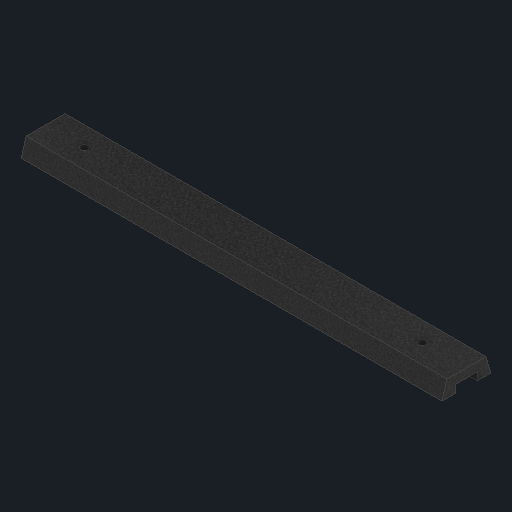
# Autodesk Inventor part: c8n_vixen_bar
Saved by Autodesk Inventor 2027.1 (Build 311270010, 270A)
## iProperties
Created: 2026-11-04
Part Number: c8n_vixen_bar
Material: Generic
Description: Vixen dovetail bar, 380 mm
Document SubType Name: Modeling
Designer: Claude (from photos)
Density: 1 g/cm^3
Appearance: Black Cast
Author: alexg
Autodesk Inventor part; units mm, degrees
ref_plane "Work Plane1" through (180, 0, 0) normal (1, 0, 0) x (0, 1, 0)
sketch "Vixen dovetail 44 wide sketch" plane through (180, 0, 0) normal (1, 0, 0) x (0, 1, 0)
  line L0 (-146, -22) -> (-146, 22)
  line L1 (-146, 22) -> (-131, 17.6005)
  line L2 (-131, 17.6005) -> (-131, -17.6005)
  line L3 (-131, -17.6005) -> (-146, -22)
  constraints: 8 end point
extrude "Vixen dovetail 44 wide" add sketch "Vixen dovetail 44 wide sketch" along normal blind 380
ref_plane "Work Plane2" through (180, 0, 0) normal (1, 0, 0) x (0, 1, 0)
sketch "Bottom channel sketch" plane through (180, 0, 0) normal (1, 0, 0) x (0, 1, 0)
  line L0 (-146, -10) -> (-139, -10)
  line L1 (-139, -10) -> (-139, 10)
  line L2 (-139, 10) -> (-146, 10)
  line L3 (-146, 10) -> (-146, -10)
  constraints: 8 end point, 2 parallel, 1 horizontal, 1 perpendicular
extrude "Bottom channel" cut sketch "Bottom channel sketch" along normal blind 380
ref_plane "Work Plane3" through (0, -146, 0) normal (0, 1, 0) x (-1, 0, 0)
sketch "Ring bolt holes sketch" plane through (0, -146, 0) normal (0, 1, 0) x (-1, 0, 0)
  circle A0 centre (-215, 0) radius 3.3
  circle A1 centre (-520, 0) radius 3.3
  constraints: 2 centre point
extrude "Ring bolt holes" cut sketch "Ring bolt holes sketch" along normal blind 15
body "Solid1"
